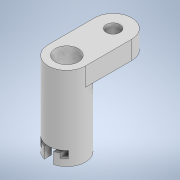
# Autodesk Inventor part: suport_reed_harta
Saved by Autodesk Inventor 2022.6 (Build 266554000, 554)
## iProperties
Created: 2025-09-29
Part Number: suport_reed_harta
Material: Generic
Document SubType Name: Modeling
Designer: Dragos Macovei
Density: 1 g/cm^3
Appearance: Default
Author: Dragos Macovei
Autodesk Inventor part; units mm, degrees
ref_plane "YZ Plane" through (0, 0, 0) normal (1, 0, 0) x (0, 1, 0)
ref_plane "XZ Plane" through (0, 0, 0) normal (0, 1, 0) x (-1, 0, 0)
ref_plane "XY Plane" through (0, 0, 0) normal (0, 0, 1) x (1, 0, 0)
sketch "Sketch1" plane through (0, 0, 0) normal (0, 1, 0) x (-1, 0, 0)
  circle A0 centre (0, 0) radius 2.5
  circle A1 centre (0, 0) radius 4
  dimension "d0" = 5
  dimension "d1" = 8
  constraints: 2 centre point, 2 coincident
  measures "d0" diameter of A0
  measures "d1" diameter of A1
extrude "Extrusion1" add sketch "Sketch1" along normal blind 18
sketch "Sketch2" plane through (0, 18, 0) normal (0, 1, 0) x (1, 0, 0)
  circle A0 centre (0, 0) radius 4
  circle A1 centre (0, 10) radius 4
  circle A2 centre (0, 0) radius 4 projected
  circle A3 centre (0, 10) radius 1.5
  line L0 (-4, 0) -> (-4, 10)
  line L1 (4, 0) -> (4, 10)
  point P0 (-2.4988, 13.1235)
  point P1 (2.4988, 13.1235)
  dimension "d6" = 3
  dimension "d9" = 10
  dimension "d10" = 8
  dimension "d11" = 8
  constraints: 6 point on circle, 4 end point, 4 tangent, 3 centre point, 2 coincident
  measures "d6" diameter of A3
  measures "d9" distance of A1.centre point (0, 0)
  measures "d10" diameter of A1
  measures "d11" diameter of A0
extrude "Extrusion2" add sketch "Sketch2" against normal blind 4 contours A0 L0 A1 L1 | A1
sketch "Sketch3" plane through (0, 0, 0) normal (0, 0, 1) x (1, 0, 0)
  line L0 (4, 14) -> (4, 18) projected
  line L1 (-4, 18) -> (4, 18) projected
  line L2 (-4, 14) -> (-4, 18) projected
  line L3 (-4, 14) -> (4, 14) projected
  line L4 (4, 0) -> (-4, 0) projected
  line L5 (4, 0) -> (4, 18) projected
  line L6 (-4, 0) -> (-4, 18) projected
  line L7 (0, 0) -> (1, 0)
  line L8 (1, 0) -> (1, 3)
  line L9 (1, 3) -> (0, 3)
  line L10 (0, 3) -> (0, 0)
  line L11 (0, 0) -> (-1, 0)
  line L12 (-1, 0) -> (-1, 3)
  line L13 (-1, 3) -> (0, 3)
  line L14 (0, 3) -> (0, 0)
  dimension "d12" = 1
  dimension "d13" = 3
  dimension "d14" = 1
  constraints: 16 end point, 4 parallel, 2 horizontal, 2 perpendicular, 1 point on line
  measures "d12" distance of L9.end L8.end
  measures "d13" distance of L8.end L7.end
  measures "d14" distance of L12.end L13.end
extrude "Extrusion3" cut sketch "Sketch3" along normal blind 15 contours L4 L10 L9 L8 | L12 L13 L10 L4
sketch "Sketch4" plane through (0, 0, 0) normal (0, 0, 1) x (1, 0, 0)
  line L0 (-1, 3) -> (1, 3) projected
  line L1 (1, 3) -> (3, 3)
  line L2 (3, 3) -> (3, 1.5)
  line L3 (3, 1.5) -> (1, 1.5)
  line L4 (1, 1.5) -> (1, 3)
  line L5 (-1, 3) -> (-3, 3)
  line L6 (-3, 3) -> (-3, 1.5)
  line L7 (-3, 1.5) -> (-1, 1.5)
  line L8 (-1, 1.5) -> (-1, 3)
  point P0 (0, 0)
  dimension "d17" = 2
  dimension "d18" = 1.5
  dimension "d19" = 2
  dimension "d20" = 1.5
  constraints: 16 end point, 4 parallel, 2 horizontal, 2 perpendicular
  measures "d17" distance of L2.end L3.end
  measures "d18" distance of L1.end L2.end
  measures "d19" distance of L7.end L6.end
  measures "d20" distance of L6.end L5.end
extrude "Extrusion4" cut sketch "Sketch4" along normal blind 15
sketch "Sketch5" plane through (-3, 1.5, 0) normal (0, 1, 0) x (1, 0, 0)
  line L0 (2, -2.2913) -> (2, -3.873) projected
  arc A0 (4, -3.873) -> (2, -3.873) centre (3, 0) ccw projected
  line L1 (4, -3.873) -> (4, -2.2913) projected
  arc A1 (4, -2.2913) -> (2, -2.2913) centre (3, 0) ccw projected
  arc A2 (4, -2.2913) -> (2, -2.2913) centre (3, 0) ccw projected
  line L2 (1, -1.5) -> (1, -3.4641)
  arc A3 (4, -3.873) -> (2, -3.873) centre (3, 0) ccw projected
  line L3 (5, -1.5) -> (5, -3.4641)
  dimension "d23" = 1
  dimension "d24" = 1
  constraints: 4 end point, 4 point on circle, 2 vertical
  measures "d23" distance between parallel lines of L0 L2
  measures "d24" distance between parallel lines of L1 L3
extrude "Extrusion5" add sketch "Sketch5" along normal blind 1 contours L0 A0 L2 A1 | L3 A0 L1 A1
equation "\"d10\" = d11"
body "Solid1"
